Autodesk Fusion 360 part; units mm, degrees
(part 2 of 2)
sketch "Sketch1" plane through (0, 0, 0) normal (0, 0, 1) x (1, 0, 0)
  line L0 (7.625, -14.5) -> (-7.625, -14.5)
  line L1 (-7.625, -14.5) -> (-7.625, 14.5)
  line L2 (-7.625, 14.5) -> (7.625, 14.5)
  line L3 (7.625, 14.5) -> (7.625, -14.5)
  line L4 (7.625, -14.5) -> (-7.625, 14.5) construction
  line L5 (-7.625, -14.5) -> (7.625, 14.5) construction
  circle A0 centre (0, 0) radius 5.845
  line L6 (-6.335, -5.24) -> (6.335, -5.24)
  arc A1 (6.335, -5.24) -> (6.335, -2.66) centre (6.335, -3.95) ccw
  line L7 (6.335, -2.66) -> (-6.335, -2.66)
  arc A2 (-6.335, -2.66) -> (-6.335, -5.24) centre (-6.335, -3.95) ccw
  line L8 (-7.625, -3.95) -> (7.625, -3.95) construction
  line L9 (0, 0) -> (7.625, 0) construction
  line L10 (6.335, 2.66) -> (-6.335, 2.66)
  arc A3 (-6.335, 5.24) -> (-6.335, 2.66) centre (-6.335, 3.95) ccw
  line L11 (-6.335, 5.24) -> (6.335, 5.24)
  arc A4 (6.335, 2.66) -> (6.335, 5.24) centre (6.335, 3.95) ccw
  dimension "d1" = 15.25
  dimension "d2" = 29
  dimension "d3" = 11.69
  dimension "d6" = 3.95
  dimension "d7" = 2.58
  constraint horizontal L0
  constraint perpendicular L0 L1
  constraint parallel L0 L2
  constraint parallel L1 L3
  constraint coincident L4 A0.centre
  constraint coincident L5 A0.centre
  constraint coincident A0.centre L9.start
  constraint tangent L6 A1
  constraint tangent A1 L7
  constraint parallel L6 L7
  constraint tangent L7 A2
  constraint tangent L6 A2
  constraint midpoint A2 L8.start
  constraint midpoint A1 L8.end
  constraint coincident L3 L8.end
  constraint perpendicular L3 L8
  constraint coincident L1 L8.start
  constraint midpoint L3 L9.end
  constraint symmetric L6.start L9 A3.start
  constraint symmetric L6.end L9 L11.end
  constraint symmetric A1.end L9 L10.start
  constraint symmetric L7.end L9 L10.end
  constraint symmetric A1 L9 A4
  constraint symmetric A2 L9 A3
  measures "d1" distance of L1.end L2.end
  measures "d2" distance of L0.start L2.end
  measures "d3" diameter of A0
  measures "d6" distance of A0.centre L8
  measures "d7" distance of L6 L7
extrude "Extrude1" add sketch "Sketch1" against normal blind 17.25 makes body 1
extrude "Extrude2" add sketch "Sketch1" against normal blind 2 from surface at -17.25 contours A0 L6 A1 L7 | A0 L6 L7 A2 | A0 L10 L11 A4 | A0 L10 A3 L11 | A0 L6 L7 | A0 L10 L11 bodies 1
extrude "Extrude3" add sketch "Sketch1" along normal blind 10.45 contours A0 L6 L7 | A0 L6 | A0 L7 L10 | A0 L10 L11 | A0 L11 bodies 1
thread "Thread1" "ISO Metric profile 12.0 M12x0.5 6g" major diameter 11.927 minor diameter 11.348 pitch 0.5 angle 60 resizes the face on face at (5.816, -0.582, 3.4833) on bodies 1
sketch "Sketch2" plane through (0, 0, 10.45) normal (0, 0, 1) x (-1, 0, 0)
  circle A0 centre (0, 0) radius 5.9635
  circle A1 centre (0, 0) radius 2.25
  dimension "d13" = 4.5
  constraint concentric A0 A1
  measures "d13" diameter of A1
ref_plane "WorkPlane1" through (0, 0, 27.05) normal (0, 0, 1) x (-1, 0, 0)
sketch "Sketch3" plane through (0, 0, 27.05) normal (0, 0, 1) x (1, 0, 0)
  circle A0 centre (0, 0) radius 2.96
  dimension "d15" = 5.92
  constraint coincident A0.centre origin
  measures "d15" diameter of A0
loft "Loft1" add profiles "Sketch2", "Sketch3" section 1 contours A1 section 2 separate body makes body 2
fillet "Fillet1" radius 1.5 1 edges at (-2.7597, 1.0704, 27.05) on bodies 2
move_body "Move1" bodies 2 to x (1, 0, 0) y (0, 0.976296, -0.21644) z (0, 0.21644, 0.976296) at (0, -2.2618, 0.2477)
extrude "Extrude4" add 1 faces at (0.1619, 0.6816, 10.2989) along direction (0, -0.21644, -0.976296) blind 2.5 on bodies 2 bodies 2
equation "d6 = ( 7.9 / 2 ) * 1 mm"

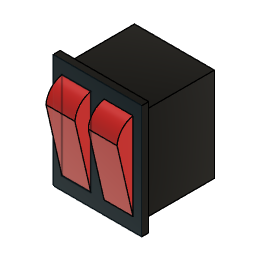
design "Dual Rocker Switch"
Autodesk Fusion 360 part; units mm, degrees
sketch "Sketch1" plane through (0, 0, 0) normal (0, 1, 0) x (1, 0, 0)
  line L0 (10.9855, 12.8905) -> (-10.9855, 12.8905)
  line L1 (-10.9855, 12.8905) -> (-10.9855, -12.8905)
  line L2 (-10.9855, -12.8905) -> (10.9855, -12.8905)
  line L3 (10.9855, -12.8905) -> (10.9855, 12.8905)
  line L4 (10.9855, 12.8905) -> (-10.9855, -12.8905) construction
  line L5 (-10.9855, 12.8905) -> (10.9855, -12.8905) construction
  dimension "d1" = 21.971
  dimension "d2" = 25.781
  constraint horizontal L0
  constraint perpendicular L0 L1
  constraint parallel L0 L2
  constraint parallel L1 L3
  constraint coincident L4 origin
  constraint coincident L5 origin
  measures "d1" distance of L1.end L2.end
  measures "d2" distance of L0.start L2.end
extrude "Extrude1" add sketch "Sketch1" along normal blind 19.2786
sketch "Sketch2" plane through (0, 0, 0) normal (0, -1, 0) x (1, 0, 0)
  line L0 (10.9855, -12.8905) -> (10.9855, 12.8905)
  line L1 (10.9855, 12.8905) -> (-10.9855, 12.8905)
  line L2 (-10.9855, 12.8905) -> (-10.9855, -12.8905)
  line L3 (-10.9855, -12.8905) -> (10.9855, -12.8905)
  line L4 (12.192, -15.621) -> (-12.192, -15.621)
  line L5 (-12.192, -15.621) -> (-12.192, 15.621)
  line L6 (-12.192, 15.621) -> (12.192, 15.621)
  line L7 (12.192, 15.621) -> (12.192, -15.621)
  line L8 (12.192, -15.621) -> (-12.192, 15.621) construction
  line L9 (-12.192, -15.621) -> (12.192, 15.621) construction
  dimension "d5" = 24.384
  dimension "d6" = 31.242
  constraint horizontal L4
  constraint perpendicular L4 L5
  constraint parallel L4 L6
  constraint parallel L5 L7
  constraint coincident L8 origin
  constraint coincident L9 origin
  measures "d5" distance of L5.end L6.end
  measures "d6" distance of L4.end L5.end
extrude "Extrude2" add sketch "Sketch2" along normal blind 1.905 contours L0 L1 L2 L3 | L4 L5 L6 L7
sketch "Sketch3" plane through (0, -1.905, 0) normal (0, -1, 0) x (1, 0, 0)
  line L0 (12.192, 15.621) -> (-12.192, 15.621)
  line L1 (-12.192, 15.621) -> (-12.192, -15.621)
  line L2 (-12.192, -15.621) -> (12.192, -15.621)
  line L3 (12.192, -15.621) -> (12.192, 15.621)
  line L4 (-9.779, 12.0142) -> (-1.8288, 12.0142)
  line L5 (-1.8288, 12.0142) -> (-1.8288, -12.0142)
  line L6 (-1.8288, -12.0142) -> (-9.779, -12.0142)
  line L7 (-9.779, -12.0142) -> (-9.779, 12.0142)
  dimension "d9" = 3.6068
  dimension "d10" = 3.6068
  dimension "d11" = 2.413
  dimension "d12" = 7.9502
  constraint horizontal L4
  constraint vertical L5
  constraint horizontal L6
  constraint vertical L7
  measures "d9" distance of L0 L4
  measures "d10" distance of L2 L6
  measures "d11" distance of L1 L7
  measures "d12" distance of L4.start L4.end
ref_plane "WorkPlane1" through (-1.8288, -1.905, 0) normal (-1, 0, 0) x (0, 0, -1)
sketch "Sketch5" plane through (-1.8288, -1.905, 0) normal (-1, 0, 0) x (0, 1, 0)
  line L0 (0, -12.0142) -> (0, 12.0142)
  line L1 (0, 12.0142) -> (-4.3758, -7.048)
  arc A0 (-4.3758, -7.048) -> (0, -12.0142) centre (1.0537, -6.6748) ccw
  dimension "d14" = 19.558
  constraint coincident L0.end L1.start
  constraint coincident L0.start A0.end
  measures "d14" distance of L0.end L1.end
extrude "Extrude3" add sketch "Sketch5" along normal blind 7.9502
mirror "Mirror1" about plane through (0, 0, 0) normal (1, 0, 0) of "Extrude3"
equation "d10 = d9"

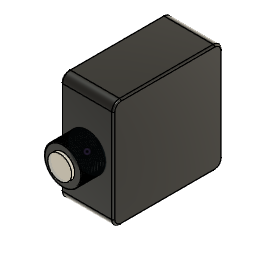
design "Tycon Circuit Breaker"
Autodesk Fusion 360 part; units mm, degrees
sketch "Sketch1" plane through (0, 0, 0) normal (0, 1, 0) x (1, 0, 0)
  line L0 (8.375, 17.45) -> (-8.375, 17.45)
  line L1 (-8.375, 17.45) -> (-8.375, -17.45)
  line L2 (-8.375, -17.45) -> (8.375, -17.45)
  line L3 (8.375, -17.45) -> (8.375, 17.45)
  line L4 (8.375, 17.45) -> (-8.375, -17.45) construction
  line L5 (-8.375, 17.45) -> (8.375, -17.45) construction
  dimension "d1" = 16.75
  dimension "d2" = 34.9
  constraint horizontal L0
  constraint perpendicular L0 L1
  constraint parallel L0 L2
  constraint parallel L1 L3
  constraint coincident L4 origin
  constraint coincident L5 origin
  measures "d1" distance of L1.end L2.end
  measures "d2" distance of L0.end L1.end
extrude "Extrude1" add sketch "Sketch1" along normal blind 35
sketch "Sketch2" plane through (0, 0, 0) normal (0, 1, 0) x (1, 0, 0)
  circle A0 centre (0, 0) radius 5.9
  dimension "d5" = 11.8
  constraint coincident A0.centre origin
  measures "d5" diameter of A0
extrude "Extrude2" add sketch "Sketch2" against normal blind 7.8
thread "Thread1" "ANSI Metric M Profile 12.0 M12x0.5 6g" major diameter 11.927 minor diameter 11.348 pitch 0.5 angle 60 modelled right hand crest width 0.0671 on face at (5.8707, -5.2, 0.5875) crest through (5.9635, 0.125, 0)
sketch "Sketch3" plane through (0, -7.8, 0) normal (0, -1, 0) x (1, 0, 0)
  spline S0 degree 3 poles (-5.3809, 1.8001) (-5.6333, 1.1023) (-5.7464, 0.3618) (-5.6834, -1.1281) (-5.5052, -1.863) (-4.8754, -3.2301) (-4.4274, -3.8481) (-3.3155, -4.8833) (-2.6605, -5.2886) (-1.4445, -5.7466) (-0.9193, -5.8662) (0.1522, -5.9611) (0.6936, -5.935) (1.2242, -5.8365) knots 0 0 0 0 0.222617 0.222617 0.447285 0.447285 0.674004 0.674004 0.902773 0.902773 1.063493 1.063493 1.22522 1.22522 1.22522 1.22522
  arc A0 (1.2242, -5.8365) -> (5.1726, -2.9678) centre (0, 0) ccw
  spline S1 degree 3 poles (5.1726, -2.9678) (5.5416, -2.2887) (5.7751, -1.5443) (5.9415, -0.0146) (5.8755, 0.7557) (5.4526, 2.2206) (5.1023, 2.9019) (4.1636, 4.0856) (3.5863, 4.5783) (2.4768, 5.2003) (1.9907, 5.3918) (0.9834, 5.6372) (0.4671, 5.6908) (-0.0492, 5.6738) knots 0 0 0 0 0.23188 0.23188 0.461709 0.461709 0.689485 0.689485 0.915208 0.915208 1.071357 1.071357 1.226496 1.226496 1.226496 1.226496
  arc A1 (-0.0492, 5.6738) -> (-5.3809, 1.8001) centre (0, 0) ccw
  circle A2 centre (0, 0) radius 3.825
  dimension "d8" = 7.65
  constraint concentric A0 A2
  measures "d8" diameter of A2
extrude "Extrude3" add sketch "Sketch3" along normal blind 1 contours A2
fillet "Fillet1" radius 2.5 4 edges at (0, 0, 17.45) (0, 35, 17.45) (0, 35, -17.45) (0, 0, -17.45)
fillet "Fillet1" radius 0.5 8 edges at (-8.375, 17.5, 17.45) (8.375, 17.5, 17.45) (8.375, 17.5, -17.45) (-8.375, 17.5, -17.45) (8.375, 0, 0) (-8.375, 0, 0) (-8.375, 35, 0) (8.375, 35, 0)
